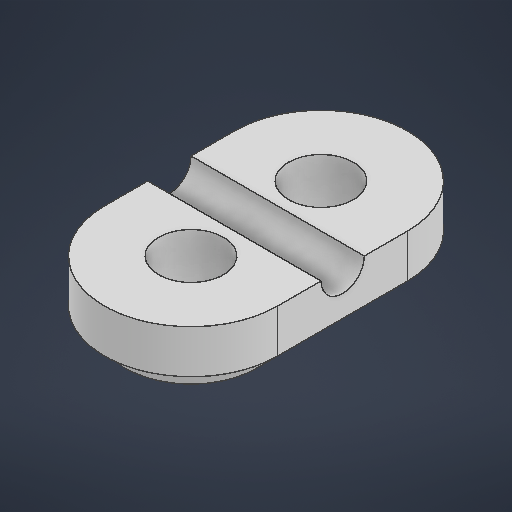
# Autodesk Inventor part: signal machine-st
Saved by Autodesk Inventor 2026.2 (Build 302298010, 298A)
## iProperties
Created: 2026-05-04
Part Number: signal machine-st
Material: 일반
Document SubType Name: Modeling
Designer: work
Density: 1 g/cm^3
Appearance: 기본값
Author: work
Autodesk Inventor part; units mm, degrees
ref_plane "YZ Plane" through (0, 0, 0) normal (1, 0, 0) x (0, 1, 0)
ref_plane "XZ Plane" through (0, 0, 0) normal (0, 1, 0) x (-1, 0, 0)
ref_plane "XY Plane" through (0, 0, 0) normal (0, 0, 1) x (1, 0, 0)
sketch "스케치1" plane through (0, 0, 0) normal (0, 1, 0) x (-1, 0, 0)
  line L0 (0, 0) -> (0, -6) construction
  circle A0 centre (0, 0) radius 1.5
  circle A1 centre (0, -6) radius 1.5
  line L1 (0, 0) -> (0, -6) construction
  line L2 (-4, 0) -> (-4, -6)
  line L3 (4, -6) -> (4, 0)
  arc A2 (4, 0) -> (-4, 0) centre (0, 0) ccw
  arc A3 (-4, -6) -> (4, -6) centre (0, -6) ccw
  point P0 (0, -3)
  dimension "d0" = 6
  dimension "d1" = 3
  dimension "d2" = 3
  dimension "d3" = 4
  constraints: 10 end point, 4 centre point, 4 point on circle, 4 tangent, 2 coincident, 2 equal length, 2 midpoint, 1 vertical
  measures "d0" distance of L0.start L0.end
  measures "d1" diameter of A0
  measures "d2" diameter of A1
  measures "d3" radius of A3
extrude "돌출1" add sketch "스케치1" along normal blind 3
sketch "스케치2" plane through (4, 0, 0) normal (1, 0, 0) x (0, 0, -1)
  line L0 (6, 3) -> (0, 3) projected
  circle A0 centre (3, 3) radius 1
  point P0 (0, 0)
  point P1 (2, 3)
  point P2 (4, 3)
  dimension "d6" = 2
  constraints: 1 centre point, 1 midpoint
  measures "d6" diameter of A0
extrude "돌출2" cut sketch "스케치2" against normal through all contours A0 L0 picked at (3.3236, 2.3716)
chamfer "모따기1" distance 1 angle 45 4 edges at (4, 0, -3) (0, 0, -10) (-4, 0, -3) (0, 0, 4)
